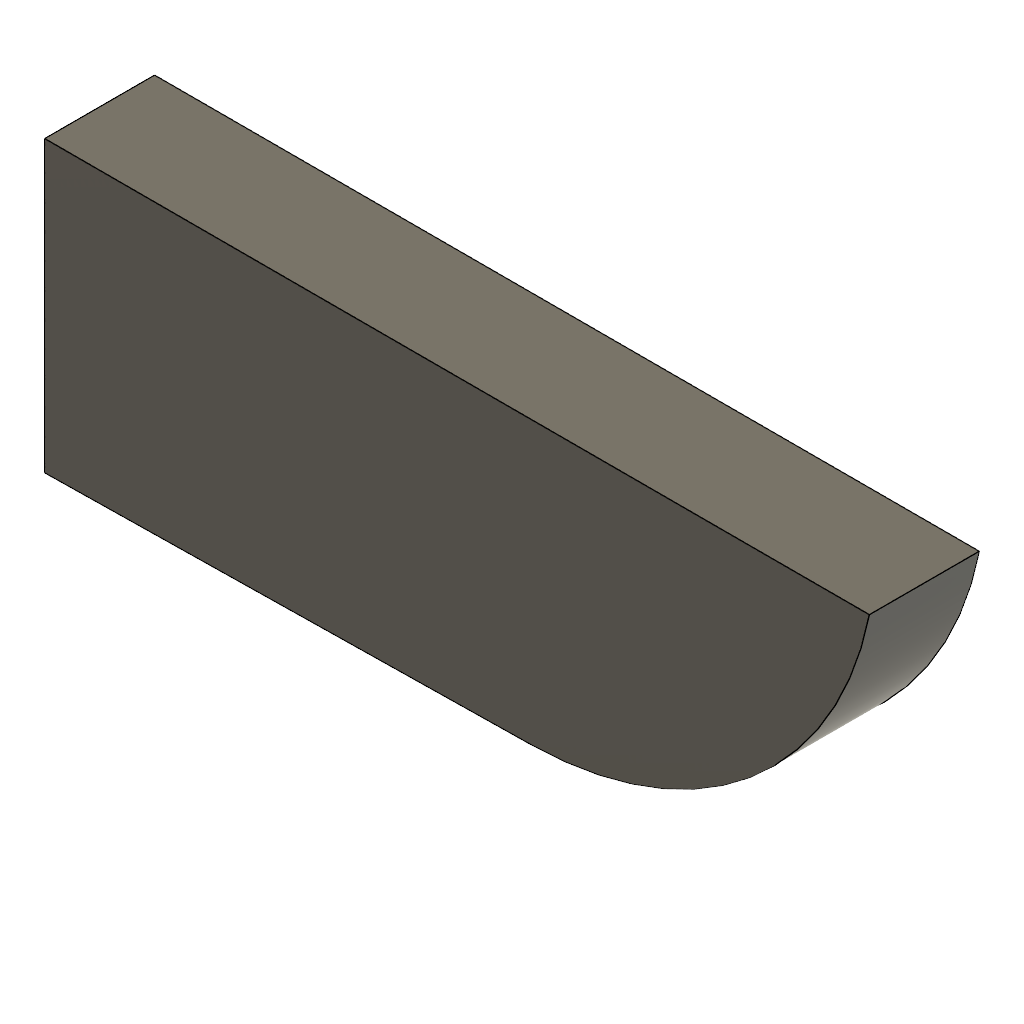
sk_arc_tangent (Autodesk Fusion 360 design; units mm, degrees)
part number: 2026-11-13-14-36-38-171
Autodesk Fusion 360 part; units mm, degrees
sketch "Sketch1" plane through (0, 0, 0) normal (0, 0, 1) x (1, 0, 0)
  line L0 (0, -0.5298) -> (17.7043, -0.2459)
  arc A0 (17.7043, -0.2459) -> (30, 10) centre (17.5, 12.5) ccw
  line L1 (30, 10) -> (0, 10)
  line L2 (0, 10) -> (0, -0.5298)
  constraint tangent L0 A0
extrude "Extrude1" add sketch "Sketch1" along normal blind 4
